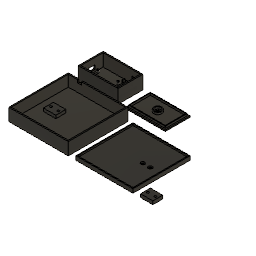
matt (Autodesk Fusion 360 design; units mm, degrees)
part number: 2026-10-25-22-13-56-036
Autodesk Fusion 360 part; units mm, degrees
sketch "Boceto1" plane through (0, 0, 0) normal (0, 0, 1) x (1, 0, 0)
  line L0 (0, 0) -> (120, 0)
  line L1 (120, 0) -> (120, 120)
  line L2 (120, 120) -> (0, 120)
  line L3 (0, 120) -> (0, 0)
extrude "Extruir1" add sketch "Boceto1" along normal blind 25 makes body 1
ref_plane "PlanoDeObra1" through (0, 0, 2.5) normal (0, 0, 1) x (1, 0, 0)
sketch "Boceto2" plane through (0, 0, 2.5) normal (0, 0, 1) x (1, 0, 0)
  line L0 (2.5, 2.5) -> (117.5, 2.5)
  line L1 (117.5, 2.5) -> (117.5, 117.5)
  line L2 (117.5, 117.5) -> (2.5, 117.5)
  line L3 (2.5, 117.5) -> (2.5, 2.5)
extrude "Extruir2" cut sketch "Boceto2" along normal blind 23.5 bodies 1
ref_plane "PlanoDeObra2" through (0, 0, 2) normal (0, 0, 1) x (1, 0, 0)
sketch "Boceto3" plane through (0, 0, 2) normal (0, 0, 1) x (1, 0, 0)
  line L0 (20, 50) -> (45, 50)
  line L1 (45, 50) -> (45, 70)
  line L2 (45, 70) -> (20, 70)
  line L3 (20, 70) -> (20, 50)
extrude "Extruir3" add sketch "Boceto3" along normal blind 6.5 bodies 1
ref_plane "PlanoDeObra3" through (0, 0, -1) normal (0, 0, 1) x (1, 0, 0)
sketch "Boceto4" plane through (0, 0, -1) normal (0, 0, 1) x (1, 0, 0)
  circle A0 centre (25, 60) radius 2.15
extrude "Extruir4" cut sketch "Boceto4" along normal blind 10.5 bodies 1
sketch "Boceto5" plane through (0, 0, -1) normal (0, 0, 1) x (1, 0, 0)
  circle A0 centre (25, 60) radius 4
extrude "Extruir5" cut sketch "Boceto5" along normal blind 3.5 bodies 1
sketch "Boceto6" plane through (0, 0, -1) normal (0, 0, 1) x (1, 0, 0)
  circle A0 centre (40, 60) radius 2.15
extrude "Extruir6" cut sketch "Boceto6" along normal blind 10.5 bodies 1
sketch "Boceto7" plane through (0, 0, -1) normal (0, 0, 1) x (1, 0, 0)
  circle A0 centre (40, 60) radius 4
extrude "Extruir7" cut sketch "Boceto7" along normal blind 3.5 bodies 1
ref_plane "PlanoDeObra4" through (0, 0, 19) normal (0, 0, 1) x (1, 0, 0)
sketch "Boceto8" plane through (0, 0, 19) normal (0, 0, 1) x (1, 0, 0)
  line L0 (21, 116.5) -> (29, 116.5)
  line L1 (29, 116.5) -> (29, 121)
  line L2 (29, 121) -> (21, 121)
  line L3 (21, 121) -> (21, 116.5)
extrude "Extruir8" cut sketch "Boceto8" along normal blind 7 bodies 1
sketch "Boceto9" plane through (0, 0, 0) normal (0, 0, 1) x (1, 0, 0)
  line L0 (135, 0) -> (250, 0)
  line L1 (250, 0) -> (250, 115)
  line L2 (250, 115) -> (135, 115)
  line L3 (135, 115) -> (135, 0)
extrude "Extruir9" add sketch "Boceto9" along normal blind 8 separate body makes body 2
ref_plane "PlanoDeObra5" through (0, 0, 5) normal (0, 0, 1) x (1, 0, 0)
sketch "Boceto10" plane through (0, 0, 5) normal (0, 0, 1) x (1, 0, 0)
  line L0 (137, 2) -> (248, 2)
  line L1 (248, 2) -> (248, 113)
  line L2 (248, 113) -> (137, 113)
  line L3 (137, 113) -> (137, 2)
extrude "Extruir10" cut sketch "Boceto10" along normal blind 4 bodies 2
sketch "Boceto11" plane through (0, 0, -1) normal (0, 0, 1) x (1, 0, 0)
  circle A0 centre (227.5, 57.5) radius 2.15
extrude "Extruir11" cut sketch "Boceto11" along normal blind 7 bodies 2
sketch "Boceto12" plane through (0, 0, 2.5) normal (0, 0, 1) x (1, 0, 0)
  circle A0 centre (227.5, 57.5) radius 4
extrude "Extruir12" cut sketch "Boceto12" along normal blind 3.5 bodies 2
sketch "Boceto13" plane through (0, 0, -1) normal (0, 0, 1) x (1, 0, 0)
  circle A0 centre (212.5, 57.5) radius 2.15
extrude "Extruir13" cut sketch "Boceto13" along normal blind 7 bodies 2
sketch "Boceto14" plane through (0, 0, 2.5) normal (0, 0, 1) x (1, 0, 0)
  circle A0 centre (212.5, 57.5) radius 4
extrude "Extruir14" cut sketch "Boceto14" along normal blind 3.5 bodies 2
sketch "Boceto15" plane through (0, 0, 0) normal (0, 0, 1) x (1, 0, 0)
  line L0 (265, 0) -> (290, 0)
  line L1 (290, 0) -> (290, 20)
  line L2 (290, 20) -> (265, 20)
  line L3 (265, 20) -> (265, 0)
extrude "Extruir15" add sketch "Boceto15" along normal blind 6.8 separate body makes body 3
sketch "Boceto16" plane through (0, 0, -1) normal (0, 0, 1) x (1, 0, 0)
  circle A0 centre (285, 10) radius 2.15
extrude "Extruir16" cut sketch "Boceto16" along normal blind 8.8 bodies 3
sketch "Boceto17" plane through (0, 0, -1) normal (0, 0, 1) x (1, 0, 0)
  circle A0 centre (270, 10) radius 2.15
extrude "Extruir17" cut sketch "Boceto17" along normal blind 8.8 bodies 3
sketch "Boceto18" plane through (0, 0, 0) normal (0, 0, 1) x (1, 0, 0)
  line L0 (0, 140) -> (80, 140)
  line L1 (80, 140) -> (80, 190)
  line L2 (80, 190) -> (0, 190)
  line L3 (0, 190) -> (0, 140)
extrude "Extruir18" add sketch "Boceto18" along normal blind 27.5 separate body makes body 4
sketch "Boceto19" plane through (0, 0, 2.5) normal (0, 0, 1) x (1, 0, 0)
  line L0 (2.5, 142.5) -> (77.5, 142.5)
  line L1 (77.5, 142.5) -> (77.5, 187.5)
  line L2 (77.5, 187.5) -> (2.5, 187.5)
  line L3 (2.5, 187.5) -> (2.5, 142.5)
extrude "Extruir19" cut sketch "Boceto19" along normal blind 26 bodies 4
sketch "Boceto20" plane through (0, 0, 2) normal (0, 0, 1) x (1, 0, 0)
  circle A0 centre (6.7, 157.4) radius 2.25
extrude "Extruir20" add sketch "Boceto20" along normal blind 5.5 bodies 4
sketch "Boceto21" plane through (0, 0, 2.5) normal (0, 0, 1) x (1, 0, 0)
  circle A0 centre (6.7, 157.4) radius 0.8
extrude "Extruir21" cut sketch "Boceto21" along normal blind 6 bodies 4
sketch "Boceto22" plane through (0, 0, 2) normal (0, 0, 1) x (1, 0, 0)
  circle A0 centre (6.7, 172.6) radius 2.25
extrude "Extruir22" add sketch "Boceto22" along normal blind 5.5 bodies 4
sketch "Boceto23" plane through (0, 0, 2.5) normal (0, 0, 1) x (1, 0, 0)
  circle A0 centre (6.7, 172.6) radius 0.8
extrude "Extruir23" cut sketch "Boceto23" along normal blind 6 bodies 4
sketch "Boceto24" plane through (0, 0, 2) normal (0, 0, 1) x (1, 0, 0)
  circle A0 centre (47.3, 157.4) radius 2.25
extrude "Extruir24" add sketch "Boceto24" along normal blind 5.5 bodies 4
sketch "Boceto25" plane through (0, 0, 2.5) normal (0, 0, 1) x (1, 0, 0)
  circle A0 centre (47.3, 157.4) radius 0.8
extrude "Extruir25" cut sketch "Boceto25" along normal blind 6 bodies 4
sketch "Boceto26" plane through (0, 0, 2) normal (0, 0, 1) x (1, 0, 0)
  circle A0 centre (47.3, 172.6) radius 2.25
extrude "Extruir26" add sketch "Boceto26" along normal blind 5.5 bodies 4
sketch "Boceto27" plane through (0, 0, 2.5) normal (0, 0, 1) x (1, 0, 0)
  circle A0 centre (47.3, 172.6) radius 0.8
extrude "Extruir27" cut sketch "Boceto27" along normal blind 6 bodies 4
ref_plane "PlanoDeObra6" through (0, 0, 6.6) normal (0, 0, 1) x (1, 0, 0)
sketch "Boceto28" plane through (0, 0, 6.6) normal (0, 0, 1) x (1, 0, 0)
  line L0 (-1, 159) -> (3, 159)
  line L1 (3, 159) -> (3, 171)
  line L2 (3, 171) -> (-1, 171)
  line L3 (-1, 171) -> (-1, 159)
extrude "Extruir28" cut sketch "Boceto28" along normal blind 8 bodies 4
sketch "Boceto29" plane through (0, 0, 2) normal (0, 0, 1) x (1, 0, 0)
  line L0 (53, 148) -> (56, 148)
  line L1 (56, 148) -> (56, 182)
  line L2 (56, 182) -> (53, 182)
  line L3 (53, 182) -> (53, 148)
extrude "Extruir29" add sketch "Boceto29" along normal blind 3.5 bodies 4
sketch "Boceto30" plane through (0, 0, 2) normal (0, 0, 1) x (1, 0, 0)
  line L0 (71, 148) -> (74, 148)
  line L1 (74, 148) -> (74, 182)
  line L2 (74, 182) -> (71, 182)
  line L3 (71, 182) -> (71, 148)
extrude "Extruir30" add sketch "Boceto30" along normal blind 3.5 bodies 4
sketch "Boceto31" plane through (0, 0, 2) normal (0, 0, 1) x (1, 0, 0)
  line L0 (50.7, 148) -> (52.7, 148)
  line L1 (52.7, 148) -> (52.7, 153)
  line L2 (52.7, 153) -> (50.7, 153)
  line L3 (50.7, 153) -> (50.7, 148)
extrude "Extruir31" add sketch "Boceto31" along normal blind 7.5 bodies 4
sketch "Boceto32" plane through (0, 0, 2) normal (0, 0, 1) x (1, 0, 0)
  line L0 (50.7, 177) -> (52.7, 177)
  line L1 (52.7, 177) -> (52.7, 182)
  line L2 (52.7, 182) -> (50.7, 182)
  line L3 (50.7, 182) -> (50.7, 177)
extrude "Extruir32" add sketch "Boceto32" along normal blind 7.5 bodies 4
sketch "Boceto33" plane through (0, 0, 2) normal (0, 0, 1) x (1, 0, 0)
  line L0 (74.3, 148) -> (76.3, 148)
  line L1 (76.3, 148) -> (76.3, 153)
  line L2 (76.3, 153) -> (74.3, 153)
  line L3 (74.3, 153) -> (74.3, 148)
extrude "Extruir33" add sketch "Boceto33" along normal blind 7.5 bodies 4
sketch "Boceto34" plane through (0, 0, 2) normal (0, 0, 1) x (1, 0, 0)
  line L0 (74.3, 177) -> (76.3, 177)
  line L1 (76.3, 177) -> (76.3, 182)
  line L2 (76.3, 182) -> (74.3, 182)
  line L3 (74.3, 182) -> (74.3, 177)
extrude "Extruir34" add sketch "Boceto34" along normal blind 7.5 bodies 4
sketch "Boceto35" plane through (0, 0, 2) normal (0, 0, 1) x (1, 0, 0)
  line L0 (60.5, 145.7) -> (66.5, 145.7)
  line L1 (66.5, 145.7) -> (66.5, 147.7)
  line L2 (66.5, 147.7) -> (60.5, 147.7)
  line L3 (60.5, 147.7) -> (60.5, 145.7)
extrude "Extruir35" add sketch "Boceto35" along normal blind 7.5 bodies 4
sketch "Boceto36" plane through (0, 0, 2) normal (0, 0, 1) x (1, 0, 0)
  line L0 (60.5, 182.3) -> (66.5, 182.3)
  line L1 (66.5, 182.3) -> (66.5, 184.3)
  line L2 (66.5, 184.3) -> (60.5, 184.3)
  line L3 (60.5, 184.3) -> (60.5, 182.3)
extrude "Extruir36" add sketch "Boceto36" along normal blind 7.5 bodies 4
ref_plane "PlanoDeObra7" through (0, 0, 9.5) normal (0, 0, 1) x (1, 0, 0)
sketch "Boceto37" plane through (0, 0, 9.5) normal (0, 0, 1) x (1, 0, 0)
  line L0 (60.5, 186.5) -> (66.5, 186.5)
  line L1 (66.5, 186.5) -> (66.5, 191)
  line L2 (66.5, 191) -> (60.5, 191)
  line L3 (60.5, 191) -> (60.5, 186.5)
extrude "Extruir37" cut sketch "Boceto37" along normal blind 6 bodies 4
sketch "Boceto38" plane through (0, 0, 0) normal (0, 0, 1) x (1, 0, 0)
  line L0 (95, 140) -> (175, 140)
  line L1 (175, 140) -> (175, 190)
  line L2 (175, 190) -> (95, 190)
  line L3 (95, 190) -> (95, 140)
extrude "Extruir38" add sketch "Boceto38" along normal blind 2.5 separate body makes body 5
sketch "Boceto39" plane through (0, 0, 2) normal (0, 0, 1) x (1, 0, 0)
  line L0 (97.8, 142.8) -> (172.2, 142.8)
  line L1 (172.2, 142.8) -> (172.2, 187.2)
  line L2 (172.2, 187.2) -> (97.8, 187.2)
  line L3 (97.8, 187.2) -> (97.8, 142.8)
extrude "Extruir39" add sketch "Boceto39" along normal blind 4.5 bodies 5
sketch "Boceto40" plane through (0, 0, 2.5) normal (0, 0, 1) x (1, 0, 0)
  line L0 (99.3, 144.3) -> (170.7, 144.3)
  line L1 (170.7, 144.3) -> (170.7, 185.7)
  line L2 (170.7, 185.7) -> (99.3, 185.7)
  line L3 (99.3, 185.7) -> (99.3, 144.3)
extrude "Extruir40" cut sketch "Boceto40" along normal blind 5 bodies 5
sketch "Boceto41" plane through (0, 0, 2) normal (0, 0, 1) x (1, 0, 0)
  circle A0 centre (135, 165) radius 8
extrude "Extruir41" add sketch "Boceto41" along normal blind 4.5 bodies 5
sketch "Boceto42" plane through (0, 0, 2.5) normal (0, 0, 1) x (1, 0, 0)
  circle A0 centre (135, 165) radius 6.15
extrude "Extruir42" cut sketch "Boceto42" along normal blind 5 bodies 5
sketch "Boceto43" plane through (0, 0, -1) normal (0, 0, 1) x (1, 0, 0)
  circle A0 centre (135, 165) radius 1
extrude "Extruir43" cut sketch "Boceto43" along normal blind 4.5 bodies 5
sketch "Boceto44" plane through (0, 0, -1) normal (0, 0, 1) x (1, 0, 0)
  circle A0 centre (138.5, 165) radius 1
extrude "Extruir44" cut sketch "Boceto44" along normal blind 4.5 bodies 5
sketch "Boceto45" plane through (0, 0, -1) normal (0, 0, 1) x (1, 0, 0)
  circle A0 centre (136.75, 168.0311) radius 1
extrude "Extruir45" cut sketch "Boceto45" along normal blind 4.5 bodies 5
sketch "Boceto46" plane through (0, 0, -1) normal (0, 0, 1) x (1, 0, 0)
  circle A0 centre (133.25, 168.0311) radius 1
extrude "Extruir46" cut sketch "Boceto46" along normal blind 4.5 bodies 5
sketch "Boceto47" plane through (0, 0, -1) normal (0, 0, 1) x (1, 0, 0)
  circle A0 centre (131.5, 165) radius 1
extrude "Extruir47" cut sketch "Boceto47" along normal blind 4.5 bodies 5
sketch "Boceto48" plane through (0, 0, -1) normal (0, 0, 1) x (1, 0, 0)
  circle A0 centre (133.25, 161.9689) radius 1
extrude "Extruir48" cut sketch "Boceto48" along normal blind 4.5 bodies 5
sketch "Boceto49" plane through (0, 0, -1) normal (0, 0, 1) x (1, 0, 0)
  circle A0 centre (136.75, 161.9689) radius 1
extrude "Extruir49" cut sketch "Boceto49" along normal blind 4.5 bodies 5
named bodies: "Base", "Plato", "Separador_plato", "Caja_control", "Tapa_control"
